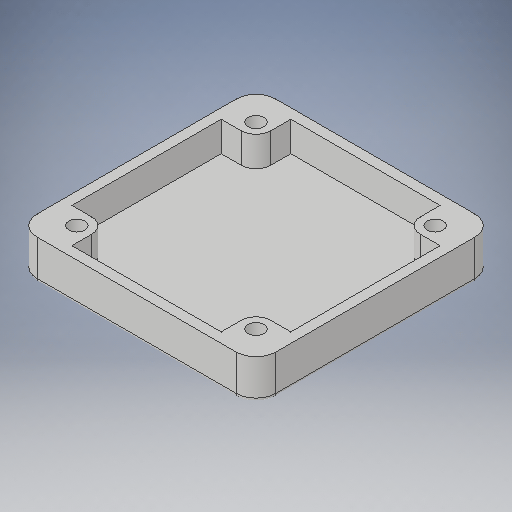
# Autodesk Inventor part: BT002_bensen22_26
Saved by Autodesk Inventor 2025 (Build 290162000, 162)
## iProperties
Company: HTBLA Kaindorf
RuleStatus: InUse
Created: 2026-08-06
Part Number: BT002_bensen22_26
Project: Biegeroboter
Material: Generisch
Description: gehäuse_motor_deckel_v1
Document SubType Name: Modeling
Designer: bensen22
Density: 1 g/cm^3
Appearance: Vorgabe
Mass: 130.76 g
Surface Area: 484.173 cm^2
Volume: 130.76 cm^3
AfterDocNew0: iProperties-Editor_aufrufen
Author: sebas
Keywords: 2026
Autodesk Inventor part; units mm, degrees
ref_plane "YZ Plane" through (0, 0, 0) normal (1, 0, 0) x (0, 1, 0)
ref_plane "XZ Plane" through (0, 0, 0) normal (0, 1, 0) x (-1, 0, 0)
ref_plane "XY Plane" through (0, 0, 0) normal (0, 0, 1) x (1, 0, 0)
sketch "Skizze3" plane through (0, 0, 0) normal (0, 0, 1) x (1, 0, 0)
  line L0 (-59.9808, -49.9423) -> (-59.9808, 50.0577)
  line L1 (-49.9808, 60.0577) -> (50.0192, 60.0577)
  line L2 (60.0192, 50.0577) -> (60.0192, -49.9423)
  line L3 (50.0192, -59.9423) -> (-49.9808, -59.9423)
  arc A0 (-59.9808, -49.9423) -> (-49.9808, -59.9423) centre (-49.9808, -49.9423) ccw
  arc A1 (-49.9808, 60.0577) -> (-59.9808, 50.0577) centre (-49.9808, 50.0577) ccw
  arc A2 (60.0192, 50.0577) -> (50.0192, 60.0577) centre (50.0192, 50.0577) ccw
  arc A3 (50.0192, -59.9423) -> (60.0192, -49.9423) centre (50.0192, -49.9423) ccw
  arc A4 (-49.9808, 55.0577) -> (-54.9808, 50.0577) centre (-49.9808, 50.0577) ccw
  line L4 (-49.9808, 55.0577) -> (50.0192, 55.0577)
  arc A5 (55.0192, 50.0577) -> (50.0192, 55.0577) centre (50.0192, 50.0577) ccw
  line L5 (55.0192, 50.0577) -> (55.0192, -49.9423)
  arc A6 (50.0192, -54.9423) -> (55.0192, -49.9423) centre (50.0192, -49.9423) ccw
  line L6 (50.0192, -54.9423) -> (-49.9808, -54.9423)
  arc A7 (-54.9808, -49.9423) -> (-49.9808, -54.9423) centre (-49.9808, -49.9423) ccw
  line L7 (-54.9808, -49.9423) -> (-54.9808, 50.0577)
  line L8 (0.0192, 86.9572) -> (0.0192, -86.8418) construction
  line L9 (-86.8803, 0.0577) -> (86.9187, 0.0577) construction
  arc A8 (45.0192, -37.4423) -> (37.5192, -44.9423) centre (45.0192, -44.9423) ccw
  line L10 (45.0192, -37.4423) -> (55.0192, -37.4423)
  line L11 (37.5192, -44.9423) -> (37.5192, -54.9423)
  arc A9 (37.5192, 45.0577) -> (45.0192, 37.5577) centre (45.0192, 45.0577) ccw
  line L12 (45.0192, 37.5577) -> (55.0192, 37.5577)
  line L13 (37.5192, 45.0577) -> (37.5192, 55.0577)
  arc A10 (-37.4808, -44.9423) -> (-44.9808, -37.4423) centre (-44.9808, -44.9423) ccw
  line L14 (-44.9808, -37.4423) -> (-54.9808, -37.4423)
  line L15 (-37.4808, -44.9423) -> (-37.4808, -54.9423)
  line L16 (-44.9808, 37.5577) -> (-54.9808, 37.5577)
  arc A11 (-44.9808, 37.5577) -> (-37.4808, 45.0577) centre (-44.9808, 45.0577) ccw
  line L17 (-37.4808, 45.0577) -> (-37.4808, 55.0577)
  point P0 (0, 0)
  dimension "d4" = 10
  dimension "d5" = 120
  dimension "d6" = 120
  dimension "d7" = 5
  dimension "d8" = 60
  dimension "d9" = 60
  dimension "d21" = 10
  dimension "d22" = 10
  dimension "d23" = 15
  constraints: 36 end point, 24 point on circle, 18 symmetric about line, 12 centre point, 10 tangent, 4 parallel, 4 perpendicular, 3 equal radius, 2 point on line, 1 coincident, 10 other
  measures "d4" radius of A0
  measures "d5" distance between parallel lines of L1 L3
  measures "d6" distance between parallel lines of L0 L2
  measures "d7" distance between parallel lines of L2 L5
  measures "d8" distance between parallel lines of L1 L9
  measures "d9" distance between parallel lines of L8 L2
  measures "d21" distance from line of L5 point (45.019, -44.942)
  measures "d22" distance from line of L6 point (45.019, -44.942)
  measures "d23" diameter of A8
extrude "Extrusion3" add sketch "Skizze3" along normal blind 20
extrude "Extrusion4" add sketch "Skizze3" along normal blind 5 contours L4 L17 A11 L16 L7 A4 | L4 L13 A9 L12 L5 L10 A8 L11 L6 L15 A10 L14 L7 L16 A11 L17 | L4 A5 L5 L12 A9 L13 | L14 A10 L15 L6 A7 L7 | L5 A6 L6 L11 A8 L10
fillet "Rundung1" radius 2 8 edges at (-57.0518, 57.1287, 0) (-59.9808, 0.0577, 0) (-57.0518, -57.0134, 0) (0.0192, -59.9423, 0) (57.0903, -57.0134, 0) (60.0192, 0.0577, 0) (57.0903, 57.1287, 0) (0.0192, 60.0577, 0)
sketch "Skizze4" plane through (0, 0, 0) normal (0, 0, -1) x (-1, 0, 0)
  circle A0 centre (0.2497, 0.1055) radius 58
  circle A1 centre (0.2497, 0.1055) radius 57.5
  circle A2 centre (0.2497, 0.1055) radius 31
  circle A3 centre (0.2497, 0.1055) radius 31.5
  circle A4 centre (0.2497, 0.1055) radius 16.25
  circle A5 centre (0.2497, 25.1055) radius 3.15
  circle A6 centre (-17.4279, 17.7832) radius 3
  circle A7 centre (-24.7503, 0.1055) radius 3
  circle A8 centre (-17.4279, -17.5721) radius 3
  circle A9 centre (0.2497, -24.8945) radius 3
  circle A10 centre (0.2497, -24.8945) radius 2.5
  circle A11 centre (17.9274, -17.5721) radius 3
  circle A12 centre (25.2497, 0.1055) radius 3
  circle A13 centre (17.9274, 17.7832) radius 3
  circle A14 centre (0.2497, 0.1055) radius 15.75
  line L0 (0.2497, 57.6055) -> (0.2497, -57.3945)
  line L1 (-57.2503, 0.1055) -> (57.7497, 0.1055)
  point P0 (0, 0)
  dimension "d17" = 116
  dimension "d18" = 115
  constraints: 15 centre point, 4 end point, 4 point on circle, 1 perpendicular, 1 vertical
  measures "d17" diameter of A0
  measures "d18" diameter of A1
extrude "Extrusion5" add sketch "Skizze4" along normal blind 6.5 contours L1 A12 A4 L0 A5 A2 | A2 L0 A9 A4 L1 A12 | L0 A5 A4 L1 A7 A2 | A2 L1 A7 A4 L0 A9
extrude "Extrusion6" add sketch "Skizze3" along normal blind 20 contours L4 L17 A11 L16 L7 A4 | L4 A5 L5 L12 A9 L13 | L14 A10 L15 L6 A7 L7 | L5 A6 L6 L11 A8 L10
hole "Bohrung1" at (45.0192, -44.9423, 0) at (45.0192, 45.0577, 0) at (-44.9808, -44.9423, 0) at (-44.9808, 45.0577, 0) direction (0, 0, 1) diameter 8 end through all
equation "\"d4\" = d10"
equation "\"d7\" = d11"
equation "\"d8\" = 0.5 * d5"
equation "\"d9\" = 0.5 * d6"
equation "\"d10\" = 10"
equation "\"d11\" = 5"
